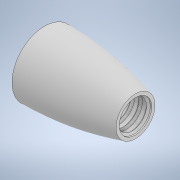
# Autodesk Inventor part: Par1t1
Saved by Autodesk Inventor 2022.6 (Build 266554000, 554)
## iProperties
Created: 2026-09-02
Part Number: Par1t1
Material: Generic
Document SubType Name: Modeling
Designer: Dragos Macovei
Density: 1 g/cm^3
Appearance: Default
Author: Dragos Macovei
Autodesk Inventor part; units mm, degrees
ref_plane "YZ Plane" through (0, 0, 0) normal (1, 0, 0) x (0, 1, 0)
ref_plane "XZ Plane" through (0, 0, 0) normal (0, 1, 0) x (-1, 0, 0)
ref_plane "XY Plane" through (0, 0, 0) normal (0, 0, 1) x (1, 0, 0)
sketch "Sketch1" plane through (0, 0, 0) normal (0, 1, 0) x (-1, 0, 0)
  line L0 (242.0587, 0) -> (242.0587, -6.25)
  line L1 (242.0587, -6.25) -> (242.0587, -12.5)
  line L2 (207.0587, 0) -> (207.0587, -7.5)
  line L3 (242.0587, -6.25) -> (207.0587, -6.25)
  arc A0 (207.0587, -7.5) -> (242.0587, -12.5) centre (242.0304, 112.3017) ccw
  line L4 (242.0587, -6.25) -> (241.3516, -5.5429)
  line L5 (242.0587, -6.25) -> (243.0587, -6.25) construction
  line L6 (241.3516, -5.5429) -> (240.6445, -6.25)
  line L7 (239.0587, -6.25) -> (238.3516, -5.5429)
  line L8 (238.3516, -5.5429) -> (237.6445, -6.25)
  line L9 (236.0587, -6.25) -> (235.3516, -5.5429)
  line L10 (235.3516, -5.5429) -> (234.6445, -6.25)
  line L11 (233.0587, -6.25) -> (232.3516, -5.5429)
  line L12 (232.3516, -5.5429) -> (231.6445, -6.25)
  line L13 (230.0587, -6.25) -> (229.3516, -5.5429)
  line L14 (229.3516, -5.5429) -> (228.6445, -6.25)
  line L15 (227.0587, -6.25) -> (226.3516, -5.5429)
  line L16 (226.3516, -5.5429) -> (225.6445, -6.25)
  line L17 (224.0587, -6.25) -> (223.3516, -5.5429)
  line L18 (223.3516, -5.5429) -> (222.6445, -6.25)
  line L19 (221.0587, -6.25) -> (220.3516, -5.5429)
  line L20 (220.3516, -5.5429) -> (219.6445, -6.25)
  line L21 (218.0587, -6.25) -> (217.3516, -5.5429)
  line L22 (217.3516, -5.5429) -> (216.6445, -6.25)
  line L23 (215.0587, -6.25) -> (214.3516, -5.5429)
  line L24 (214.3516, -5.5429) -> (213.6445, -6.25)
  line L25 (212.0587, -6.25) -> (211.3516, -5.5429)
  line L26 (211.3516, -5.5429) -> (210.6445, -6.25)
  line L27 (209.0587, -6.25) -> (208.3516, -5.5429)
  line L28 (208.3516, -5.5429) -> (207.6445, -6.25)
  line L29 (242.0587, 0) -> (207.0587, 0)
  point P0 (0, 0)
  dimension "d0" = 6.25
  dimension "d1" = 6.25
  dimension "d2" = 7.5
  dimension "d3" = 35
  dimension "d4" = 1
  dimension "d5" = 135
  dimension "d6" = 90
  dimension "d9" = 3
  constraints: 58 end point, 33 horizontal alignment, 22 parallel, 3 vertical, 2 horizontal, 2 point on circle, 2 point on line, 1 centre point, 1 equal length, 4 other
  measures "d0" distance of L0.start L0.end
  measures "d1" distance of L0.end L1.end
  measures "d2" distance of L2.start L2.end
  measures "d3" distance between parallel lines of L2 L0
  measures "d4" distance of L0.end L4.end
  measures "d5" angle of L5 L4
  measures "d6" angle of L6 L4
  measures "d9" distance of L0.end L7.start
revolve "Revolution1" add sketch "Sketch1" angle 360 about axis through (-242.0587, 0, 0) along (1, 0, 0) contours L1 A0 L2 L3 | L3 L6 L4 | L3 L8 L7 | L28 L27 L3 | L3 L10 L9 | L26 L25 L3 | L3 L12 L11 | L24 L23 L3 | L3 L14 L13 | L22 L21 L3 | L3 L16 L15 | L20 L19 L3 | L3 L18 L17
sketch "Sketch2" plane through (-242.0587, 0, 0) normal (-1, 0, 0) x (0, 0, 1)
  point P0 (0, 0)
body "Solid1"
